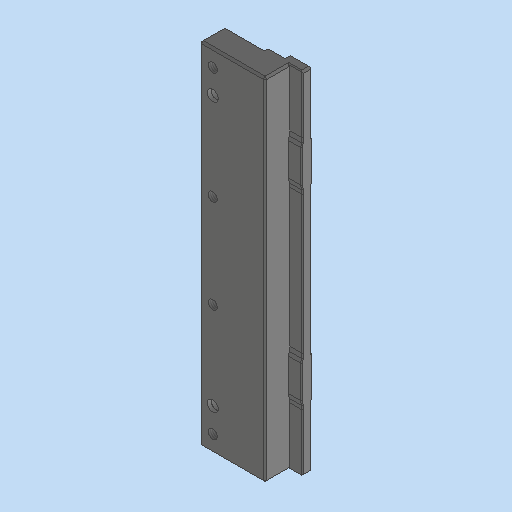
# Autodesk Inventor part: MM0937AN100_G16_157
Saved by Autodesk Inventor 2023.3 (Build 273359000, 359)
## iProperties
Created: 2024-03-19
Part Number: MM0937AN100_G16_157
Material: 1.2099 X5CrS12
Description: =<RBPARTNOTITLE2>
Document SubType Name: Modeling
Designer: RIC7AN
Mass: 741.891 g
Surface Area: 239.479 cm^2
Volume: 94.5084 cm^3
Density: 7.85 g/cm^3
Appearance: Stahl - rostfrei AnP
RBPARTMADEOF: 188 x 18,3 x 42 (FM)
RBDRAWINGMISSINGSPEC: --
AnP_Kategorie: 1
RBPARTNOTITLE2: Anfertigungsteil
RBSURFACE: --
RBPARTNOTITLE1: manufactured part
RBSURFACE2: --
AnP_Material: =<Material>
RBMATERIAL: =<Material>
RBMATNO: =<Part Number>
RBPARTNO: SIEHE MNR
MaxAbmaße: 188 x 18,3 x 42 (FM)
Author: RIC7AN
Keywords: =<RBPARTMADEOF>
Comments: =<RBSURFACE2>
Revision Number: 01
Autodesk Inventor part; units mm, degrees
ref_plane "YZ Plane" through (0, 0, 0) normal (1, 0, 0) x (0, 1, 0)
ref_plane "XZ Plane" through (0, 0, 0) normal (0, 1, 0) x (-1, 0, 0)
ref_plane "XY Plane" through (0, 0, 0) normal (0, 0, 1) x (1, 0, 0)
sketch "Skizze1" plane through (0, 0, 0) normal (0, 0, 1) x (1, 0, 0)
  line L0 (0, 0) -> (-35, 0)
  line L1 (-35, 0) -> (-35, -12.5)
  line L2 (-35, -12.5) -> (0, -12.5)
  line L3 (0, -12.5) -> (0, 0)
  line L4 (0, 0) -> (-4.8, 0)
  line L5 (-4.8, 0) -> (-4.8, 0.2)
  line L6 (-4.8, 0.2) -> (0, 0.2)
  line L7 (0, 0.2) -> (0, 0)
  line L8 (-4.8, 0.2) -> (7, 0.2)
  line L9 (7, 0.2) -> (7, 5.8)
  line L10 (7, 5.8) -> (-4.8, 5.8)
  line L11 (-4.8, 5.8) -> (-4.8, 0.2)
  line L12 (-4.8, 0) -> (-13, 0)
  line L13 (-13, 0) -> (-13, 2)
  line L14 (-13, 2) -> (-4.8, 2)
  line L15 (-4.8, 2) -> (-4.8, 0)
  point P0 (-5, 0)
  point P1 (-4.8, 0)
  point P2 (7, 3)
  point P3 (-4.8, 2)
  point P4 (-13, 0)
  dimension "d2" = 12.5
  dimension "d3" = 5.6
  dimension "d5" = 0.2
  dimension "d44" = 7
  dimension "d46" = 35
  dimension "d47" = 11.8
  dimension "d50" = 2
  dimension "d51" = 22
  constraints: 32 end point, 8 parallel, 4 horizontal, 4 perpendicular, 1 midpoint
  measures "d2" distance of L0.end L1.end
  measures "d3" distance of L8.end L9.end
  measures "d5" distance between parallel lines of L8 L0
  measures "d44" distance between parallel lines of L3 L9
  measures "d46" distance between parallel lines of L1 L3
  measures "d47" distance from line of point (7, 3) L11
  measures "d50" distance of L12.end L13.end
  measures "d51" distance between parallel lines of L13 L1
extrude "Extrusion1" add sketch "Skizze1" along normal mid plane 188
sketch "Skizze2" plane through (-35, 0, 94) normal (0, 1, 0) x (1, 0, 0)
  line L0 (35, 225.6) -> (35, -37.6) projected
  line L1 (50.4, 94) -> (-8.4, 94) projected
  line L2 (0, 188) -> (0, 0) projected
  point P0 (35, 94)
  point P1 (7, 69)
  point P2 (7, 119)
  point P3 (7, 9)
  point P4 (7, 179)
  dimension "d8" = 170
  dimension "d9" = 50
  dimension "d10" = 7
  constraints: 2 symmetric about line, 1 vertical alignment
  measures "d8" distance of point (7, 179) point (7, 9)
  measures "d9" distance of point (7, 119) point (7, 69)
  measures "d10" distance from line of point (7, 9) L2
hole "Bohrung1" at (-28, 0, 25) at (-28, 0, -25) at (-28, 0, 85) at (-28, 0, -85) direction (0, -1, 0) diameter 4.917 end through all thread size "M6x1" designation "M6" class "6H" standard "ISO Metric profile"
sketch "Skizze3" plane through (-35, 0, 94) normal (0, 1, 0) x (1, 0, 0)
  line L0 (50.4, 94) -> (-8.4, 94) projected
  circle A0 centre (7, 179) radius 2.4585 projected
  point P0 (35, 94)
  point P1 (7, 166)
  point P2 (7, 22)
  dimension "d18" = 144
  constraints: 1 symmetric about line, 1 vertical alignment
  measures "d18" distance of point (7, 22) point (7, 166)
hole "Bohrung2" at (-28, 0, -72) at (-28, 0, 72) direction (0, -1, 0) diameter 5.8 end through all counterbore diameter 6 counterbore depth 10.5
chamfer "Fase2" distance 1 angle 45 17 edges at (7, 3, 94) (7, 3, -94) (0, -12.5, 0) (0, -6.15, 94) (-4.8, 3.9, 94) (-35, -6.25, 94) (-17.5, -12.5, 94) (-35, -12.5, 0) (-35, -6.25, -94) (-17.5, -12.5, -94) (0, -6.15, -94) (-4.8, 3.9, -94) (3.5, 0.2, 94) (1.1, 5.8, 94) (1.1, 5.8, -94) (3.5, 0.2, -94) (-13, 2, 0)
sketch "Skizze6" plane through (7, 0.2, 93) normal (1, 0, 0) x (0, 0, -1)
  line L0 (186, 5.6) -> (0, 5.6) projected
  line L1 (186, 0) -> (0, 0) projected
  line L2 (-1, 4.6) -> (0, 5.6) projected
  line L3 (-1, 4.6) -> (-1, 1) projected
  line L4 (-1, 1) -> (0, 0) projected
  line L5 (187, 4.6) -> (186, 5.6) projected
  line L6 (187, 1) -> (187, 4.6) projected
  line L7 (187, 1) -> (186, 0) projected
  line L8 (93, -16.36) -> (93, 9.26) projected
  line L9 (-1, 5.6) -> (33, 5.6)
  line L10 (33, 5.6) -> (33, 5.1)
  line L11 (33, 5.1) -> (-1, 5.1)
  line L12 (-1, 5.1) -> (-1, 5.6)
  line L13 (33, 0) -> (-1, 0)
  line L14 (-1, 0) -> (-1, 0.5)
  line L15 (-1, 0.5) -> (33, 0.5)
  line L16 (33, 0.5) -> (33, 0)
  line L17 (53, 5.6) -> (133, 5.6)
  line L18 (133, 5.6) -> (133, 5.1)
  line L19 (133, 5.1) -> (53, 5.1)
  line L20 (53, 5.1) -> (53, 5.6)
  line L21 (133, 0) -> (53, 0)
  line L22 (53, 0) -> (53, 0.5)
  line L23 (53, 0.5) -> (133, 0.5)
  line L24 (133, 0.5) -> (133, 0)
  line L25 (187, 5.6) -> (153, 5.6)
  line L26 (153, 5.6) -> (153, 5.1)
  line L27 (153, 5.1) -> (187, 5.1)
  line L28 (187, 5.1) -> (187, 5.6)
  line L29 (187, 0) -> (153, 0)
  line L30 (153, 0) -> (153, 0.5)
  line L31 (153, 0.5) -> (187, 0.5)
  line L32 (187, 0.5) -> (187, 0)
  line L33 (33, 5.1) -> (53, 5.1) construction
  line L34 (153, 5.1) -> (133, 5.1) construction
  point P0 (143, 5.1)
  point P1 (43, 5.1)
  point P2 (-0.5, 0.5)
  point P3 (93, 5.1)
  point P4 (93, 0.5)
  point P5 (53, 0)
  point P6 (186.5, 0.5)
  point P7 (153, 0)
  dimension "d55" = 100
  dimension "d56" = 20
  dimension "d57" = 20
  dimension "d58" = 0.5
  dimension "d59" = 0.5
  constraints: 52 end point, 12 parallel, 10 point on line, 8 collinear, 7 horizontal, 6 perpendicular, 2 midpoint, 1 symmetric about line
  measures "d55" distance of point (143, 5.1) point (43, 5.1)
  measures "d56" distance of L10.end L19.end
  measures "d57" distance of L26.end L18.end
  measures "d58" distance of L11.end L9.start
  measures "d59" distance of L13.end L14.end
extrude "Extrusion2" cut sketch "Skizze6" against normal up to surface (7 mm away) contours L7 L1 L30 L31 | L23 L24 L1 L8 | L8 L1 L22 L23 | L1 L4 L15 L16 | L13 L14 L15 L4
extrude "Extrusion3" cut sketch "Skizze6" against normal through all contours L5 L27 L26 L0 | L25 L28 L27 L5 | L18 L19 L8 L0 | L8 L19 L20 L0 | L10 L11 L2 L0 | L2 L11 L12 L9
fillet "Rundung1" radius 10 16 edges at (1.1, 5.3, 60) (1.1, 5.8, 60) (3.5, 0.7, 60) (3.5, 0.2, 60) (3.5, 0.7, 40) (3.5, 0.2, 40) (1.1, 5.8, 40) (1.1, 5.3, 40) (1.1, 5.3, -40) (1.1, 5.8, -40) (1.1, 5.3, -60) (1.1, 5.8, -60) (3.5, 0.7, -60) (3.5, 0.2, -60) (3.5, 0.2, -40) (3.5, 0.7, -40)
chamfer "Fase1" distance 0.5 angle 45 39 edges at (7, 5.8, -50) (7, 5.7373, -40.2036) (7, 5.3627, -37.9955) (7, 5.3, 0) (7, 5.3627, 37.9955) (7, 5.7373, 40.2036) (7, 5.8, 50) (7, 5.7373, 59.7964) (7, 5.3627, 62.0045) (7, 5.3, 78.0612) (7, 5.7373, -59.7964) (7, 5.3627, -62.0045) (7, 5.3, -78.0612) (7, 0.2, -50) (7, 0.2627, -40.2036) (7, 0.6373, -37.9955) (7, 0.7, 0) (7, 0.6373, 37.9955) (7, 0.2627, 40.2036) (7, 0.2, 50) (7, 0.2627, 59.7964) (7, 0.6373, 62.0045) (7, 0.7, 78.0612) (7, 0.2627, -59.7964) (7, 0.6373, -62.0045) (7, 0.7, -78.0612) (-4.8, 5.3, 78.0612) (-4.8, 5.3627, 62.0045) (-4.8, 5.7373, 59.7964) (-4.8, 5.8, 50) (-4.8, 5.7373, 40.2036) (-4.8, 5.3627, 37.9955) (-4.8, 5.3, 0) (-4.8, 5.3627, -37.9955) (-4.8, 5.7373, -40.2036) (-4.8, 5.8, -50) (-4.8, 5.7373, -59.7964) (-4.8, 5.3627, -62.0045) (-4.8, 5.3, -78.0612)
equation "\"d57\" = d56"
